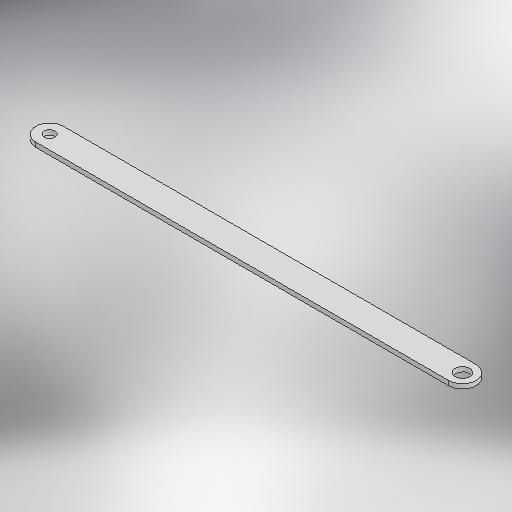
# Autodesk Inventor part: AP2.0_connect-holder
Saved by Autodesk Inventor 2025.3 (Build 293356030, 356C)
## iProperties
Created: 2026-06-06
Part Number: AP2.0_connect-holder
Material: 一般
Document SubType Name: Sheet Metal
Designer: ibuki_ono
Density: 1 g/cm^3
Sheet Metal Rule: Default_mm
Appearance: 既定
Author: ibuki_ono
Autodesk Inventor part; units mm, degrees
ref_plane "YZ Plane" through (0, 0, 0) normal (1, 0, 0) x (0, 1, 0)
ref_plane "XZ Plane" through (0, 0, 0) normal (0, 1, 0) x (-1, 0, 0)
ref_plane "XY Plane" through (0, 0, 0) normal (0, 0, 1) x (1, 0, 0)
sketch "スケッチ1" plane through (0, 0, 0) normal (0, 1, 0) x (-1, 0, 0)
  line L0 (-45, 0) -> (45, 0) construction
  line L1 (-45, -3) -> (45, -3)
  line L2 (45, 3) -> (-45, 3)
  arc A0 (-45, 3) -> (-45, -3) centre (-45, 0) ccw
  arc A1 (45, -3) -> (45, 3) centre (45, 0) ccw
  line L3 (0, 0) -> (90, 0) construction
  dimension "d0" = 45
  dimension "d1" = 0
  dimension "d2" = 6
  measures "d0" distance of L3.start L0.end
  measures "d1" distance between parallel lines of L0 L3
  measures "d2" diameter of A1
extrude "プレート1" add sketch "スケッチ1" along normal blind 1
sketch "スケッチ2" plane through (0, 1, 0) normal (0, 1, 0) x (1, 0, 0)
  arc A0 (45, -3) -> (45, 3) centre (45, 0) ccw projected
  arc A1 (-45, 3) -> (-45, -3) centre (-45, 0) ccw projected
  circle A2 centre (45, 0) radius 1.6
  circle A3 centre (-45, 0) radius 1.2
  point P0 (0, 0)
  dimension "d4" = 3.2
  dimension "d5" = 2.4
  constraints: 2 centre point, 2 coincident
  measures "d4" diameter of A2
  measures "d5" diameter of A3
extrude "押し出し1" cut sketch "スケッチ2" against normal through all
equation "\"d3\" = Thickness"
equation "\"BendRadius\" = Thickness"
equation "\"BendReliefWidth\" = Thickness"
equation "\"BendReliefDepth\" = 0.5 * Thickness"
equation "\"CornerReliefSize\" = 4 * Thickness"
equation "\"MinimumRemnant\" = 2 * Thickness"
equation "\"TransitionRadius\" = BendRadius"
equation "\"JacobiRadiusSize\" = BendRadius"
equation "\"GapSize\" = Thickness"
equation "\"Thickness\" = 1"
